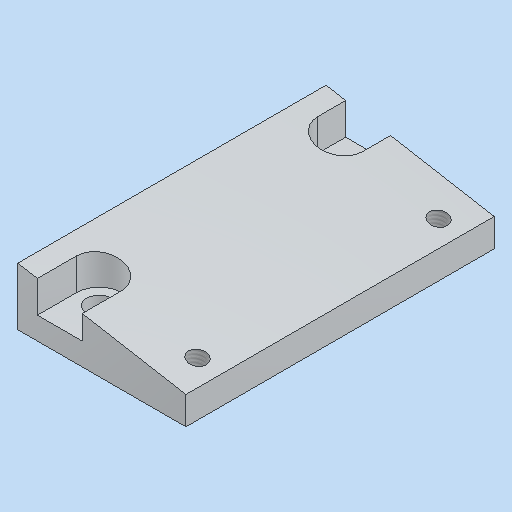
# Autodesk Inventor part: MM0948AN130_G13_102
Saved by Autodesk Inventor 2023.3 (Build 273359000, 359)
## iProperties
Created: 2024-11-11
Part Number: MM0948AN130_G13_102
Material: 3.3547 AlMg4,5Mn0,7 - AW 5083
Description: =<RBPARTNOTITLE2>
Document SubType Name: Modeling
Designer: RIC7AN
Mass: 11.6648 g
Surface Area: 49.2141 cm^2
Volume: 11.6648 cm^3
Density: 1 g/cm^3
Appearance: Aluminium AnP
RBPARTMADEOF: 55 x 10,29 x 30 (FM)
RBDRAWINGMISSINGSPEC: --
AnP_Kategorie: 1
RBPARTNOTITLE2: Anfertigungsteil
RBSURFACE: anodised colourless
RBPARTNOTITLE1: manufactured part
RBSURFACE2: eloxiert farblos
AnP_Material: =<Material>
RBMATERIAL: =<Material>
RBMATNO: =<Part Number>
RBPARTNO: SIEHE MNR
MaxAbmaße: 55 x 10,29 x 30 (FM)
Author: RIC7AN
Keywords: =<RBPARTMADEOF>
Comments: =<RBSURFACE2>
Revision Number: 01
Autodesk Inventor part; units mm, degrees
ref_plane "YZ Plane" through (0, 0, 0) normal (1, 0, 0) x (0, 1, 0)
ref_plane "XZ Plane" through (0, 0, 0) normal (0, 1, 0) x (-1, 0, 0)
sketch "Skizze1" plane through (0, 0, 0) normal (0, 0, 1) x (1, 0, 0)
  line L0 (0, 0) -> (0, 5)
  line L1 (0, 5) -> (-30, 10.2898)
  line L2 (-30, 10.2898) -> (-30, 0)
  line L3 (-30, 0) -> (0, 0)
  line L4 (-36, 0) -> (6, 0) projected
  dimension "d0" = 5
  dimension "d2" = 30
  dimension "d33" = 10
  constraints: 8 end point, 1 collinear, 1 parallel, 1 perpendicular
  measures "d0" distance of L0.start L0.end
  measures "d2" distance of L2.end L0.start
  measures "d33" angle of L3 L1
extrude "Extrusion1" add sketch "Skizze1" along normal mid plane 55
sketch "Skizze2" plane through (-30, 10.2898, 27.5) normal (0.1736, 0.9848, 0) x (0.9848, -0.1736, 0)
  line L0 (38.6077, 27.5) -> (-6.4346, 27.5) projected
  line L1 (30.4628, 0) -> (30.4628, 55) projected
  point P0 (31.331, 27.5)
  point P1 (26.4628, 49)
  point P2 (26.4628, 6)
  dimension "d5" = 43
  dimension "d6" = 4
  constraints: 1 symmetric about line
  measures "d5" distance of point (26.463, 6) point (26.463, 49)
  measures "d6" distance from line of L1 point (26.463, 49)
hole "Bohrung1" at (-3.9392, 5.6946, -21.5) at (-3.9392, 5.6946, 21.5) direction (-0.1736, -0.9848, 0) diameter 3.242 end through all thread size "M4x0.7" designation "M4" class "6H" standard "ISO Metric profile"
ref_plane "Arbeitsebene2" through (-30, 4, 27.5) normal (0, -1, 0) x (1, 0, 0)
sketch "Skizze3" plane through (10, 4, 27.5) normal (0, 1, 0) x (-1, 0, 0)
  line L0 (10, 0) -> (40, 0) projected
  line L1 (40, -55) -> (10, -55) projected
  line L2 (32.5, 0) -> (32.5, -7) construction
  line L3 (28.5, 0) -> (28.5, -7)
  line L4 (36.5, -7) -> (36.5, 0)
  arc A0 (36.5, 0) -> (28.5, 0) centre (32.5, 0) ccw
  arc A1 (28.5, -7) -> (36.5, -7) centre (32.5, -7) ccw
  line L5 (32.5, -55) -> (32.5, -50) construction
  line L6 (36.5, -55) -> (36.5, -50)
  line L7 (28.5, -50) -> (28.5, -55)
  arc A2 (28.5, -55) -> (36.5, -55) centre (32.5, -55) ccw
  arc A3 (36.5, -50) -> (28.5, -50) centre (32.5, -50) ccw
  line L8 (10, 0) -> (10, -55) projected
  line L9 (4, -27.5) -> (46, -27.5) projected
  point P0 (10, -27.5)
  point P1 (32.5, -3.5)
  point P2 (32.5, -52.5)
  point P3 (36.5, 0)
  point P4 (28.5, 0)
  dimension "d14" = 8
  dimension "d19" = 22.5
  dimension "d30" = 20.5
  dimension "d34" = 22.5
  constraints: 16 end point, 8 point on circle, 8 tangent, 4 centre point, 2 collinear, 2 midpoint, 2 parallel, 2 perpendicular, 2 point on line
  measures "d14" distance between parallel lines of L6 L7
  measures "d19" distance between parallel lines of L5 L8
  measures "d30" distance from line of L9 L2.end
  measures "d34" distance from line of L5.end L9
extrude "Extrusion2" cut sketch "Skizze3" along normal through all contours L0 L4 A1 L3 | L7 A3 L6 L1
sketch "Skizze4" plane through (10, 4, 27.5) normal (0, 1, 0) x (1, 0, 0)
  line L0 (-36.5, 55) -> (-28.5, 55) projected
  line L1 (-4, 27.5) -> (-46, 27.5) projected
  point P0 (-10, 27.5)
  point P1 (-32.5, 50)
  point P2 (-32.5, 7)
  point P3 (-32.5, 55)
  dimension "d31" = 20.5
  dimension "d32" = 22.5
  constraints: 2 vertical alignment, 1 midpoint
  measures "d31" distance from line of point (-32.5, 7) L1
  measures "d32" distance from line of L1 point (-32.5, 50)
hole "Bohrung2" at (-22.5, 4, -22.5) at (-22.5, 4, 20.5) direction (0, -1, 0) diameter 4.5 end through all clearance for "Inbusschraube ISO 4762  versenkt" size "M4" standard "ISO"
